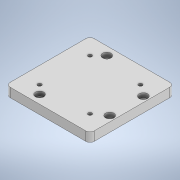
# Autodesk Inventor part: CARO adaptateur UR10 Panda
Saved by Autodesk Inventor 2020 (Build 240168000, 168)
## iProperties
Created: 2022-09-22
Part Number: CARO adaptateur UR10 Panda
Material: Générique
Document SubType Name: Modeling
Designer: Stark
Density: 1 g/cm^3
Appearance: Par défaut
Author: Stark
Autodesk Inventor part; units mm, degrees
ref_plane "YZ Plane" through (0, 0, 0) normal (1, 0, 0) x (0, 1, 0)
ref_plane "XZ Plane" through (0, 0, 0) normal (0, 1, 0) x (-1, 0, 0)
ref_plane "XY Plane" through (0, 0, 0) normal (0, 0, 1) x (1, 0, 0)
sketch "Esquisse1" plane through (0, 0, 0) normal (0, 1, 0) x (-1, 0, 0)
  line L0 (0, 0) -> (200, 0)
  line L1 (200, 0) -> (200, -200)
  line L2 (200, -200) -> (0, -200)
  line L3 (0, -200) -> (0, 0)
  dimension "d0" = 200
  dimension "d1" = 200
  constraints: 8 end point, 2 parallel, 1 horizontal, 1 perpendicular
  measures "d0" distance of L0.end L1.end
  measures "d1" distance of L1.end L2.end
extrude "Extrusion1" add sketch "Esquisse1" along normal blind 21.6
fillet "Congé1" radius 10 4 edges at (0, 10.8, 0) (0, 10.8, -200) (-200, 10.8, -200) (-200, 10.8, 0)
sketch "Esquisse6" plane through (0, 0, 0) normal (0, -1, 0) x (1, 0, 0)
  line L0 (-190, 0) -> (-10, 0) projected
  line L1 (-100, -252.5893) -> (-100, 14.0624) construction
  line L2 (-213.6062, -100) -> (44.1453, -100) construction
  line L3 (-200, -190) -> (-200, -10) construction
  point P0 (0, 0)
  point P1 (-160, -40)
  point P2 (-160, -160)
  point P3 (-40, -40)
  point P4 (-40, -160)
  dimension "d82" = 100
  dimension "d83" = 100
  dimension "d84" = 60
  dimension "d85" = 60
  constraints: 4 end point, 3 symmetric about line, 1 horizontal, 1 vertical
  measures "d82" distance between parallel lines of L3 L1
  measures "d83" distance between parallel lines of L0 L2
  measures "d84" distance from line of L2 point (-160, -40)
  measures "d85" distance from line of L1 point (-160, -40)
hole "Perçage6" at (-160, 0, -160) at (-160, 0, -40) at (-40, 0, -160) at (-40, 0, -40) direction (0, 1, 0) diameter 9 end through all counterbore diameter 20 counterbore depth 10
sketch "Esquisse7" plane through (0, 21.6, 0) normal (0, 1, 0) x (1, 0, 0)
  line L0 (-230.1234, 100) -> (23.9771, 100) construction
  line L1 (-100, -28.4052) -> (-100, 325.4937) construction
  point P0 (0, 0)
  point P1 (-140, 20)
  point P2 (-13, 60)
  point P3 (-140, 180)
  point P4 (-13, 140)
  dimension "d95" = 80
  dimension "d96" = 40
  dimension "d97" = 40
  dimension "d108" = 127
  constraints: 4 end point, 2 symmetric about line, 1 horizontal, 1 vertical
  measures "d95" distance from line of L0 point (-140, 20)
  measures "d96" distance from line of L0 point (-13, 60)
  measures "d97" distance from line of point (-140, 20) L1
  measures "d108" horizontal distance of point (-13, 60) point (-140, 20)
hole "Perçage7" at (-140, 21.6, -20) at (-13, 21.6, -60) at (-140, 21.6, -180) at (-13, 21.6, -140) direction (0, -1, 0) diameter 9 end through all counterbore diameter 20 counterbore depth 10
